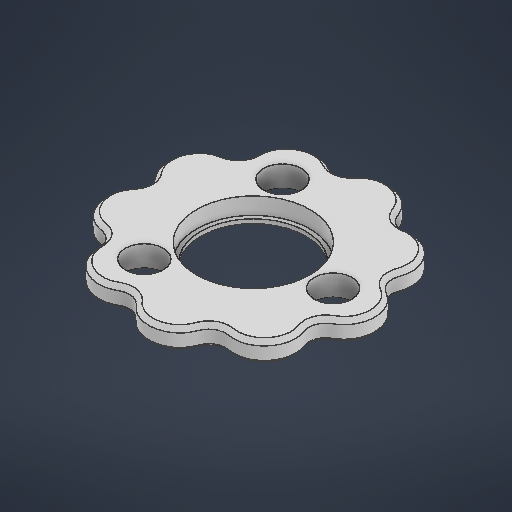
# Autodesk Inventor part: gear
Saved by Autodesk Inventor 2026.2 (Build 302298010, 298A)
## iProperties
Created: 2026-03-31
Part Number: gear
Material: 일반
Document SubType Name: Modeling
Designer: work
Density: 1 g/cm^3
Appearance: 기본값
Author: work
Autodesk Inventor part; units mm, degrees
ref_plane "YZ Plane" through (0, 0, 0) normal (1, 0, 0) x (0, 1, 0)
ref_plane "XZ Plane" through (0, 0, 0) normal (0, 1, 0) x (-1, 0, 0)
ref_plane "XY Plane" through (0, 0, 0) normal (0, 0, 1) x (1, 0, 0)
sketch "스케치1" plane through (0, 0, 0) normal (0, 1, 0) x (-1, 0, 0)
  circle A0 centre (0, 0) radius 12.5
  spline S0 degree 5 poles (25, 0) (25.001231, -0.665545) (25.152127, -1.337018) (25.4659, -1.952784) (26.159641, -2.784252) (26.771689, -3.682951) (26.977399, -4.048519) (27.397772, -4.966423) (27.640719, -5.948443) (27.721123, -6.535454) (27.769192, -7.809223) (27.55304, -9.067989) (27.364475, -9.727592) (26.8665, -10.95227) (26.125034, -12.045542) (25.714685, -12.533681) (24.911416, -13.303904) (23.975885, -13.899548) (23.554159, -14.11921) (22.692668, -14.465142) (21.786778, -14.672554) (21.341714, -14.747916) (20.057181, -15.135488) (18.997773, -15.988499) (18.478628, -16.802318) (18.237849, -18.055924) (18.211268, -19.320342) (18.180662, -19.713459) (18.039893, -20.631316) (17.740002, -21.512233) (17.516337, -21.999417) (16.914841, -23.040262) (16.113279, -23.940145) (15.616366, -24.389145) (14.535098, -25.175529) (13.313436, -25.718742) (12.676134, -25.924581) (11.496032, -26.168813) (10.293886, -26.169301) (9.76014, -26.119409) (8.847297, -25.938664) (7.982025, -25.601645) (7.626273, -25.431592) (6.517964, -24.822403) (5.31192, -24.40412) (4.34756, -24.446804) (3.079126, -24.937772) (2.101214, -25.856425) (1.813414, -26.20418) (1.180848, -26.884998) (0.450513, -27.458105) (0.049423, -27.7135) (-0.934196, -28.22587) (-2.002848, -28.536412) (-2.630784, -28.647712) (-3.948282, -28.743211) (-5.257923, -28.562122) (-5.923364, -28.395635) (-7.12169, -27.953424) (-8.200609, -27.274938) (-8.669018, -26.911759) (-9.397582, -26.210422) (-9.982819, -25.387331) (-10.195894, -25.026509) (-10.669564, -24.046884) (-11.040362, -23.030714) (-11.421038, -22.450634) (-12.423543, -21.518208) (-13.7323, -21.116225) (-14.425003, -21.076591) (-15.490431, -21.263555) (-16.575646, -21.343157) (-16.994664, -21.33904) (-18.000101, -21.243756) (-18.971758, -20.963469) (-19.520485, -20.739405) (-20.64753, -20.144276) (-21.629659, -19.327602) (-22.106562, -18.834555) (-22.91821, -17.790918) (-23.494254, -16.602182) (-23.711834, -16.002724) (-23.977222, -14.921972) (-24.025306, -13.813949) (-24.004673, -13.338897) (-23.873515, -12.419855) (-23.600193, -11.531627) (-23.442928, -11.108508) (-23.136307, -9.802285) (-23.345333, -8.458305) (-23.790548, -7.601802) (-24.755813, -6.766479) (-25.837541, -6.11125) (-26.162687, -5.888186) (-26.887191, -5.307348) (-27.500141, -4.607175) (-27.810223, -4.169884) (-28.410873, -3.128551) (-28.789413, -1.984436) (-28.929802, -1.329597) (-29.070197, 0) (-28.929802, 1.329597) (-28.789413, 1.984436) (-28.410873, 3.128551) (-27.810223, 4.169884) (-27.500141, 4.607175) (-26.887191, 5.307348) (-26.162687, 5.888186) (-25.837541, 6.11125) (-24.755813, 6.766479) (-23.790548, 7.601802) (-23.345333, 8.458305) (-23.136307, 9.802285) (-23.442928, 11.108508) (-23.600193, 11.531627) (-23.873515, 12.419855) (-24.004673, 13.338897) (-24.025306, 13.813949) (-23.977222, 14.921972) (-23.711834, 16.002724) (-23.494254, 16.602182) (-22.91821, 17.790918) (-22.106562, 18.834555) (-21.629659, 19.327602) (-20.64753, 20.144276) (-19.520485, 20.739405) (-18.971758, 20.963469) (-18.000101, 21.243756) (-16.994664, 21.33904) (-16.575646, 21.343157) (-15.490431, 21.263555) (-14.425003, 21.076591) (-13.7323, 21.116225) (-12.423543, 21.518208) (-11.421038, 22.450634) (-11.040362, 23.030714) (-10.669564, 24.046884) (-10.195894, 25.026509) (-9.982819, 25.387331) (-9.397582, 26.210422) (-8.669018, 26.911759) (-8.200609, 27.274938) (-7.12169, 27.953424) (-5.923364, 28.395635) (-5.257923, 28.562122) (-3.948282, 28.743211) (-2.630784, 28.647712) (-2.002848, 28.536412) (-0.934196, 28.22587) (0.049423, 27.7135) (0.450513, 27.458105) (1.180848, 26.884998) (1.813414, 26.20418) (2.101214, 25.856425) (3.079126, 24.937772) (4.34756, 24.446804) (5.31192, 24.40412) (6.517964, 24.822403) (7.626273, 25.431592) (7.982025, 25.601645) (8.847297, 25.938664) (9.76014, 26.119409) (10.293886, 26.169301) (11.496032, 26.168813) (12.676134, 25.924581) (13.313436, 25.718742) (14.535098, 25.175529) (15.616366, 24.389145) (16.113279, 23.940145) (16.914841, 23.040262) (17.516337, 21.999417) (17.740002, 21.512233) (18.039893, 20.631316) (18.180662, 19.713459) (18.211268, 19.320342) (18.237849, 18.055924) (18.478628, 16.802318) (18.997773, 15.988499) (20.057181, 15.135488) (21.341714, 14.747916) (21.786778, 14.672554) (22.692668, 14.465142) (23.554159, 14.11921) (23.975885, 13.899548) (24.911416, 13.303904) (25.714685, 12.533681) (26.125034, 12.045542) (26.8665, 10.95227) (27.364475, 9.727592) (27.55304, 9.067989) (27.769192, 7.809223) (27.721123, 6.535454) (27.640719, 5.948443) (27.397772, 4.966423) (26.977399, 4.048519) (26.771689, 3.682951) (26.159641, 2.784252) (25.4659, 1.952784) (25.152127, 1.337018) (25.001231, 0.665545) (25, 0) knots 0 0 0 0 0 0 0.01743247 0.01743247 0.01743247 0.02835885 0.02835885 0.02835885 0.0437346 0.0437346 0.0437346 0.06153775 0.06153775 0.06153775 0.0780942 0.0780942 0.0780942 0.09044046 0.09044046 0.09044046 0.1022994 0.1022994 0.1022994 0.12507995 0.12507995 0.12507995 0.13536277 0.13536277 0.13536277 0.14928604 0.14928604 0.14928604 0.16666667 0.16666667 0.16666667 0.18404729 0.18404729 0.18404729 0.19797057 0.19797057 0.19797057 0.20825339 0.20825339 0.20825339 0.23103394 0.23103394 0.23103394 0.24289287 0.24289287 0.24289287 0.25523913 0.25523913 0.25523913 0.27179558 0.27179558 0.27179558 0.28959873 0.28959873 0.28959873 0.30497448 0.30497448 0.30497448 0.31590086 0.31590086 0.31590086 0.33333333 0.33333333 0.33333333 0.3507658 0.3507658 0.3507658 0.36169218 0.36169218 0.36169218 0.37706794 0.37706794 0.37706794 0.39487109 0.39487109 0.39487109 0.41142753 0.41142753 0.41142753 0.42377379 0.42377379 0.42377379 0.43563273 0.43563273 0.43563273 0.45841328 0.45841328 0.45841328 0.4686961 0.4686961 0.4686961 0.48261938 0.48261938 0.48261938 0.5 0.5 0.5 0.51738062 0.51738062 0.51738062 0.5313039 0.5313039 0.5313039 0.54158672 0.54158672 0.54158672 0.56436727 0.56436727 0.56436727 0.57622621 0.57622621 0.57622621 0.58857247 0.58857247 0.58857247 0.60512891 0.60512891 0.60512891 0.62293206 0.62293206 0.62293206 0.63830782 0.63830782 0.63830782 0.6492342 0.6492342 0.6492342 0.66666667 0.66666667 0.66666667 0.68409914 0.68409914 0.68409914 0.69502552 0.69502552 0.69502552 0.71040127 0.71040127 0.71040127 0.72820442 0.72820442 0.72820442 0.74476087 0.74476087 0.74476087 0.75710713 0.75710713 0.75710713 0.76896606 0.76896606 0.76896606 0.79174661 0.79174661 0.79174661 0.80202943 0.80202943 0.80202943 0.81595271 0.81595271 0.81595271 0.83333333 0.83333333 0.83333333 0.85071396 0.85071396 0.85071396 0.86463723 0.86463723 0.86463723 0.87492005 0.87492005 0.87492005 0.8977006 0.8977006 0.8977006 0.90955954 0.90955954 0.90955954 0.9219058 0.9219058 0.9219058 0.93846225 0.93846225 0.93846225 0.9562654 0.9562654 0.9562654 0.97164115 0.97164115 0.97164115 0.98256753 0.98256753 0.98256753 1 1 1 1 1 1
  line L0 (0, 0) -> (25, 0) construction
  circle A1 centre (-19, 0) radius 4.5
  line L1 (0, 0) -> (-29, 0) construction
  circle A2 centre (0, 0) radius 19 construction
  circle A3 centre (9.5, -16.454483) radius 4.5
  circle A4 centre (9.5, 16.454483) radius 4.5
  spline S1 degree 5 poles (24.9, -0.000185) (24.900594, -0.357289) (24.943404, -0.713677) (25.028705, -1.064805) (25.281018, -1.729542) (25.65796, -2.333312) (25.86847, -2.614322) (26.298468, -3.15922) (26.680505, -3.739496) (26.851703, -4.037769) (27.149265, -4.657267) (27.364044, -5.309701) (27.45003, -5.642478) (27.580688, -6.316833) (27.629161, -7.002181) (27.633434, -7.345933) (27.602395, -8.032692) (27.494099, -8.711507) (27.421062, -9.047644) (27.238107, -9.710438) (26.983259, -10.349065) (26.838332, -10.661017) (26.514522, -11.267468) (26.124975, -11.833924) (25.914378, -12.105765) (25.462889, -12.623685) (24.953454, -13.084756) (24.685162, -13.299449) (24.123044, -13.694074) (23.514852, -14.012948) (23.200377, -14.151779) (22.549482, -14.38714) (21.875695, -14.546262) (21.534546, -14.614244) (20.848295, -14.786026) (20.200767, -15.071243) (19.890048, -15.252831) (19.315658, -15.684955) (18.85986, -16.241116) (18.666981, -16.546392) (18.361927, -17.193099) (18.204983, -17.890446) (18.159653, -18.242491) (18.126205, -18.938441) (18.083533, -19.634122) (18.042088, -19.976332) (17.91197, -20.65182) (17.694353, -21.304168) (17.564126, -21.622155) (17.264362, -22.240076) (16.891124, -22.816743) (16.68752, -23.093705) (16.248779, -23.622836) (15.752704, -24.098565) (15.491449, -24.322293) (14.945173, -24.739807) (14.356127, -25.094496) (14.052122, -25.255415) (13.427605, -25.543011) (12.77506, -25.759438) (12.44304, -25.849228) (11.770565, -25.99041) (11.086094, -26.052645) (10.742677, -26.063124) (10.056049, -26.042573) (9.378052, -25.934719) (9.042585, -25.859473) (8.382074, -25.660782) (7.750951, -25.380631) (7.444201, -25.220501) (6.82511, -24.888315) (6.168907, -24.634976) (5.824159, -24.538007) (5.114574, -24.426006) (4.399133, -24.48227) (4.044984, -24.555127) (3.365685, -24.784156) (2.755694, -25.161618) (2.47399, -25.38189) (1.96828, -25.8673) (1.499502, -26.387264) (1.262116, -26.638508) (0.751826, -27.102181) (0.188149, -27.498018) (-0.106789, -27.67471) (-0.716353, -27.990548) (-1.361264, -28.227239) (-1.690345, -28.326072) (-2.359249, -28.484214) (-3.041751, -28.564257) (-3.385096, -28.584824) (-4.0726, -28.587555) (-4.756232, -28.514071) (-5.095678, -28.458495) (-5.767058, -28.310152) (-6.417899, -28.08851) (-6.736807, -27.9597) (-7.358486, -27.666609) (-7.942489, -27.30421) (-8.2235, -27.106228) (-8.760127, -26.677555) (-9.239401, -26.185613) (-9.462961, -25.924849) (-9.875787, -25.373884) (-10.209965, -24.771976) (-10.360345, -24.461355) (-10.622159, -23.813614) (-10.913718, -23.178724) (-11.087778, -22.86783) (-11.502231, -22.2836) (-12.037383, -21.807665) (-12.335026, -21.603018) (-12.971155, -21.26932) (-13.668559, -21.095448) (-14.024922, -21.050244) (-14.730197, -21.037549) (-15.429799, -21.122944) (-15.772392, -21.179188) (-16.461142, -21.239595) (-17.151595, -21.22429) (-17.493857, -21.18927) (-18.171201, -21.078425) (-18.829296, -20.881109) (-19.151655, -20.762498) (-19.780981, -20.486304) (-20.373659, -20.138826) (-20.65985, -19.94805) (-21.209437, -19.535073) (-21.709679, -19.06342) (-21.946503, -18.813972) (-22.391696, -18.28996) (-22.776408, -17.720087) (-22.952746, -17.424766) (-23.271579, -16.815795) (-23.519377, -16.174624) (-23.624591, -15.847311) (-23.795783, -15.182065) (-23.885111, -14.500974) (-23.908329, -14.158215) (-23.91042, -13.470818) (-23.820865, -12.789303) (-23.754695, -12.451379) (-23.569996, -11.780298) (-23.359185, -11.118043) (-23.264101, -10.777775) (-23.145033, -10.074216) (-23.173557, -9.361757) (-23.23138, -9.005631) (-23.430903, -8.314662) (-23.790423, -7.692148) (-24.006408, -7.403261) (-24.49648, -6.89087) (-25.068832, -6.471195) (-25.368273, -6.290493) (-25.95203, -5.917096) (-26.498541, -5.490183) (-26.753192, -5.259097) (-27.230624, -4.765338) (-27.63972, -4.213541) (-27.826343, -3.92504) (-28.163596, -3.326476) (-28.427227, -2.692031) (-28.540448, -2.367357) (-28.729478, -1.706407) (-28.843126, -1.028414) (-28.881045, -0.686541) (-28.918954, 0) (-28.881045, 0.686541) (-28.843126, 1.028414) (-28.729478, 1.706407) (-28.540448, 2.367357) (-28.427227, 2.692031) (-28.163596, 3.326476) (-27.826343, 3.92504) (-27.63972, 4.213541) (-27.230624, 4.765338) (-26.753192, 5.259097) (-26.498541, 5.490183) (-25.95203, 5.917096) (-25.368273, 6.290493) (-25.068832, 6.471195) (-24.49648, 6.89087) (-24.006408, 7.403261) (-23.790423, 7.692148) (-23.430903, 8.314662) (-23.23138, 9.005631) (-23.173557, 9.361757) (-23.145033, 10.074216) (-23.264101, 10.777775) (-23.359185, 11.118043) (-23.569996, 11.780298) (-23.754695, 12.451379) (-23.820865, 12.789303) (-23.91042, 13.470818) (-23.908329, 14.158215) (-23.885111, 14.500974) (-23.795783, 15.182065) (-23.624591, 15.847311) (-23.519377, 16.174624) (-23.271579, 16.815795) (-22.952746, 17.424766) (-22.776408, 17.720087) (-22.391696, 18.28996) (-21.946503, 18.813972) (-21.709679, 19.06342) (-21.209437, 19.535073) (-20.65985, 19.94805) (-20.373659, 20.138826) (-19.780981, 20.486304) (-19.151655, 20.762498) (-18.829296, 20.881109) (-18.171201, 21.078425) (-17.493857, 21.18927) (-17.151595, 21.22429) (-16.461142, 21.239595) (-15.772392, 21.179188) (-15.429799, 21.122944) (-14.730197, 21.037549) (-14.024922, 21.050244) (-13.668559, 21.095448) (-12.971155, 21.26932) (-12.335026, 21.603018) (-12.037383, 21.807665) (-11.502231, 22.2836) (-11.087778, 22.86783) (-10.913718, 23.178724) (-10.622159, 23.813614) (-10.360345, 24.461355) (-10.209965, 24.771976) (-9.875787, 25.373884) (-9.462961, 25.924849) (-9.239401, 26.185613) (-8.760127, 26.677555) (-8.2235, 27.106228) (-7.942489, 27.30421) (-7.358486, 27.666609) (-6.736807, 27.9597) (-6.417899, 28.08851) (-5.767058, 28.310152) (-5.095678, 28.458495) (-4.756232, 28.514071) (-4.0726, 28.587555) (-3.385096, 28.584824) (-3.041751, 28.564257) (-2.359249, 28.484214) (-1.690345, 28.326072) (-1.361264, 28.227239) (-0.716353, 27.990548) (-0.106789, 27.67471) (0.188149, 27.498018) (0.751826, 27.102181) (1.262116, 26.638508) (1.499502, 26.387264) (1.96828, 25.8673) (2.47399, 25.38189) (2.755694, 25.161618) (3.365685, 24.784156) (4.044984, 24.555127) (4.399133, 24.48227) (5.114574, 24.426006) (5.824159, 24.538007) (6.168907, 24.634976) (6.82511, 24.888315) (7.444201, 25.220501) (7.750951, 25.380631) (8.382074, 25.660782) (9.042585, 25.859473) (9.378052, 25.934719) (10.056049, 26.042573) (10.742677, 26.063124) (11.086094, 26.052645) (11.770565, 25.99041) (12.44304, 25.849228) (12.77506, 25.759438) (13.427605, 25.543011) (14.052122, 25.255415) (14.356127, 25.094496) (14.945173, 24.739807) (15.491449, 24.322293) (15.752704, 24.098565) (16.248779, 23.622836) (16.68752, 23.093705) (16.891124, 22.816743) (17.264362, 22.240076) (17.564126, 21.622155) (17.694353, 21.304168) (17.91197, 20.65182) (18.042088, 19.976332) (18.083533, 19.634122) (18.126205, 18.938441) (18.159653, 18.242491) (18.204983, 17.890446) (18.361927, 17.193099) (18.666981, 16.546392) (18.85986, 16.241116) (19.315658, 15.684955) (19.890048, 15.252831) (20.200767, 15.071243) (20.848295, 14.786026) (21.534546, 14.614244) (21.875695, 14.546262) (22.549482, 14.38714) (23.200377, 14.151779) (23.514852, 14.012948) (24.123044, 13.694074) (24.685162, 13.299449) (24.953454, 13.084756) (25.462889, 12.623685) (25.914378, 12.105765) (26.124975, 11.833924) (26.514522, 11.267468) (26.838332, 10.661017) (26.983259, 10.349065) (27.238107, 9.710438) (27.421062, 9.047644) (27.494099, 8.711507) (27.602395, 8.032692) (27.633434, 7.345933) (27.629161, 7.002181) (27.580688, 6.316833) (27.45003, 5.642478) (27.364044, 5.309701) (27.149265, 4.657267) (26.851703, 4.037769) (26.680505, 3.739496) (26.298468, 3.15922) (25.86847, 2.614322) (25.65796, 2.333312) (25.281018, 1.729542) (25.028705, 1.064805) (24.943404, 0.713677) (24.900594, 0.357289) (24.9, 0.000185) knots 0 0 0 0 0 0 0.00936313 0.00936313 0.00936313 0.01856867 0.01856867 0.01856867 0.02756331 0.02756331 0.02756331 0.03655171 0.03655171 0.03655171 0.04555028 0.04555028 0.04555028 0.05455412 0.05455412 0.05455412 0.06355839 0.06355839 0.06355839 0.07255848 0.07255848 0.07255848 0.08154935 0.08154935 0.08154935 0.09053487 0.09053487 0.09053487 0.09967579 0.09967579 0.09967579 0.10902484 0.10902484 0.10902484 0.11839872 0.11839872 0.11839872 0.12766342 0.12766342 0.12766342 0.13667891 0.13667891 0.13667891 0.14566473 0.14566473 0.14566473 0.1546614 0.1546614 0.1546614 0.16366439 0.16366439 0.16366439 0.17266893 0.17266893 0.17266893 0.18167046 0.18167046 0.18167046 0.19066385 0.19066385 0.19066385 0.19964745 0.19964745 0.19964745 0.20872815 0.20872815 0.20872815 0.21805356 0.21805356 0.21805356 0.22743006 0.22743006 0.22743006 0.23673988 0.23673988 0.23673988 0.24579428 0.24579428 0.24579428 0.25477825 0.25477825 0.25477825 0.26377279 0.26377279 0.26377279 0.27277481 0.27277481 0.27277481 0.28177931 0.28177931 0.28177931 0.29078187 0.29078187 0.29078187 0.29977767 0.29977767 0.29977767 0.30876226 0.30876226 0.30876226 0.31779428 0.31779428 0.31779428 0.32708439 0.32708439 0.32708439 0.33645883 0.33645883 0.33645883 0.34579769 0.34579769 0.34579769 0.35490855 0.35490855 0.35490855 0.36389256 0.36389256 0.36389256 0.37288456 0.37288456 0.37288456 0.3818853 0.3818853 0.3818853 0.39088965 0.39088965 0.39088965 0.39989313 0.39989313 0.39989313 0.40889086 0.40889086 0.40889086 0.41787788 0.41787788 0.41787788 0.42688095 0.42688095 0.42688095 0.43611981 0.43611981 0.43611981 0.44548621 0.44548621 0.44548621 0.45484341 0.45484341 0.45484341 0.46401826 0.46401826 0.46401826 0.47300703 0.47300703 0.47300703 0.48199662 0.48199662 0.48199662 0.490996 0.490996 0.490996 0.5 0.5 0.5 0.509004 0.509004 0.509004 0.51800338 0.51800338 0.51800338 0.52699297 0.52699297 0.52699297 0.53598174 0.53598174 0.53598174 0.54515659 0.54515659 0.54515659 0.55451379 0.55451379 0.55451379 0.56388019 0.56388019 0.56388019 0.57311905 0.57311905 0.57311905 0.58212212 0.58212212 0.58212212 0.59110914 0.59110914 0.59110914 0.60010687 0.60010687 0.60010687 0.60911035 0.60911035 0.60911035 0.6181147 0.6181147 0.6181147 0.62711544 0.62711544 0.62711544 0.63610744 0.63610744 0.63610744 0.64509145 0.64509145 0.64509145 0.65420231 0.65420231 0.65420231 0.66354117 0.66354117 0.66354117 0.67291561 0.67291561 0.67291561 0.68220572 0.68220572 0.68220572 0.69123774 0.69123774 0.69123774 0.70022233 0.70022233 0.70022233 0.70921813 0.70921813 0.70921813 0.71822069 0.71822069 0.71822069 0.72722519 0.72722519 0.72722519 0.73622721 0.73622721 0.73622721 0.74522175 0.74522175 0.74522175 0.75420572 0.75420572 0.75420572 0.76326012 0.76326012 0.76326012 0.77256994 0.77256994 0.77256994 0.78194644 0.78194644 0.78194644 0.79127185 0.79127185 0.79127185 0.80035255 0.80035255 0.80035255 0.80933615 0.80933615 0.80933615 0.81832954 0.81832954 0.81832954 0.82733107 0.82733107 0.82733107 0.83633561 0.83633561 0.83633561 0.8453386 0.8453386 0.8453386 0.85433527 0.85433527 0.85433527 0.86332109 0.86332109 0.86332109 0.87233658 0.87233658 0.87233658 0.88160128 0.88160128 0.88160128 0.89097516 0.89097516 0.89097516 0.90032421 0.90032421 0.90032421 0.90946513 0.90946513 0.90946513 0.91845065 0.91845065 0.91845065 0.92744152 0.92744152 0.92744152 0.93644161 0.93644161 0.93644161 0.94544588 0.94544588 0.94544588 0.95444972 0.95444972 0.95444972 0.96344829 0.96344829 0.96344829 0.97243669 0.97243669 0.97243669 0.98143133 0.98143133 0.98143133 0.99063687 0.99063687 0.99063687 1 1 1 1 1 1
  dimension "d28" = 0.1
  dimension "d2" = 25
  dimension "d8" = 25
  dimension "d9" = 9
  dimension "d10" = 19
  dimension "d20" = 38
  dimension "d23" = 360
  constraints: 5 centre point, 4 end point, 3 horizontal, 2 coincident, 1 point on line, 13 other
  measures "d2" diameter of A0
  measures "d8" distance of L0.start L0.end
  measures "d9" diameter of A1
  measures "d10" distance of point (0, 0) A1.centre
  measures "d20" diameter of A2
extrude "돌출1" add sketch "스케치1" along normal blind 5 contours S1
sketch "스케치2" plane through (0, 5, 0) normal (0, 1, 0) x (1, 0, 0)
  circle A0 centre (0, 0) radius 13.5
  dimension "d17" = 27
  constraints: 1 centre point, 1 coincident
  measures "d17" diameter of A0
extrude "돌출2" cut sketch "스케치2" against normal blind 4
chamfer "모따기2" distance 1 angle 45 2 edges at (28.9, 5, 0) (28.9, 0, 0)
equation "curve S0 of \"스케치1\": x = (30 * cos(t * 1 rad) - 3 * cos(t * 1 rad + atan(sin(-9 * t * 1 rad) / ((30 / (2 * 10)) - cos(-9 * t * 1 rad)))) - 2 * cos(10 * t * 1 rad)) * 1 mm\n; y = (-30 * sin(t * 1 rad) + "
